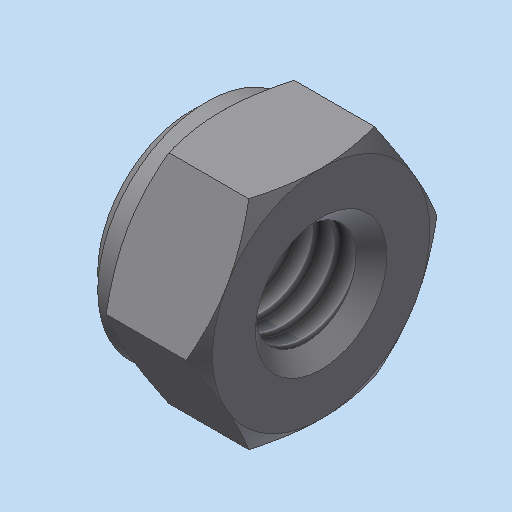
# Autodesk Inventor part: MM0861AN100_G02_512
Saved by Autodesk Inventor 2023.3 (Build 273359000, 359)
## iProperties
Created: 2018-11-29
Part Number: MM0861AN100_G02_512
Material: Generisch
Document SubType Name: Modeling
Designer: Rose
Density: 1 g/cm^3
Appearance: Vorgabe
Description: Selbstsichernde Mutter
Mass: 0.133436 g
Surface Area: 1.94665 cm^2
Volume: 0.133436 cm^3
MaxAbmaße: 0 x 0 x 0 (FM)
AnP_Material_aktuell: =<Material>
AnP_Kommentar_aktuell: =<Comments>
Author: Rose
Keywords: M4 ISO 7042
Revision Number: 01
Autodesk Inventor part; units mm, degrees
ref_plane "YZ Plane" through (0, 0, 0) normal (1, 0, 0) x (0, 1, 0)
ref_plane "XZ Plane" through (0, 0, 0) normal (0, 1, 0) x (-1, 0, 0)
ref_plane "XY Plane" through (0, 0, 0) normal (0, 0, 1) x (1, 0, 0)
sketch "Skizze1" plane through (0, 0, 0) normal (0, 0, 1) x (1, 0, 0)
  line L0 (0, 5.4) -> (0, -0.9) projected
  line L1 (-5.04, 0) -> (0.84, 0) projected
  line L2 (0, 0) -> (0, 3.5)
  line L3 (0, 3.5) -> (-0.5774, 4.5)
  line L4 (-0.5774, 4.5) -> (-2.6226, 4.5)
  line L5 (-2.6226, 4.5) -> (-3.2, 3.5)
  line L6 (-3.2, 3.5) -> (-4.2, 3.5)
  line L7 (-4.2, 3.5) -> (-4.2, 0)
  dimension "d0" = 7
  dimension "d1" = 30
  dimension "d2" = 4.2
  dimension "d3" = 3.2
  dimension "d4" = 1
  constraints: 12 end point, 5 point on line, 2 perpendicular, 1 equal length, 1 parallel
  measures "d0" diameter of L6 L1
  measures "d1" angle of L0 L3
  measures "d2" distance between parallel lines of L7 L0
  measures "d3" distance from line of L0 L5.end
  measures "d4" vertical distance of L2.end L3.end
revolve "Umdrehung1" add sketch "Skizze1" angle 360 about axis through (0, 0, 0) along (1, 0, 0)
hole "Bohrung1" at (-4.2, 0, 0) direction (1, 0, 0) diameter 3.242 end through all thread size "M4x0.7" designation "M4" class "6H" standard "ISO Metric profile"
sketch "Skizze2" plane through (0, 0, 0) normal (1, 0, 0) x (0, 0, -1)
  line L0 (-6.3, 0) -> (6.3, 0) projected
  line L1 (0, -6.3) -> (0, 6.3) projected
  circle A0 centre (0, 0) radius 4.5 projected
  line L2 (0, 4.0415) -> (3.5, 2.0207)
  line L3 (3.5, 2.0207) -> (3.5, -2.0207)
  line L4 (3.5, -2.0207) -> (0, -4.0415)
  line L5 (0, -4.0415) -> (-3.5, -2.0207)
  line L6 (-3.5, -2.0207) -> (-3.5, 2.0207)
  line L7 (-3.5, 2.0207) -> (0, 4.0415)
  dimension "d15" = 7
  constraints: 12 end point, 1 coincident, 1 point on line, 13 other
  measures "d15" distance between parallel lines of L3 L6
extrude "Extrusion1" cut sketch "Skizze2" against normal through all contours A0 L1 L7 L6 L0 | L0 L6 L5 L1 A0 | A0 L0 L3 L2 L1 | L1 L4 L3 L0 A0
chamfer "Fase1" distance 0.5 angle 45 3 edges at (0, 0, -1.621) (-4.2, 0, -1.621) (-4.2, -3.5, 0)
